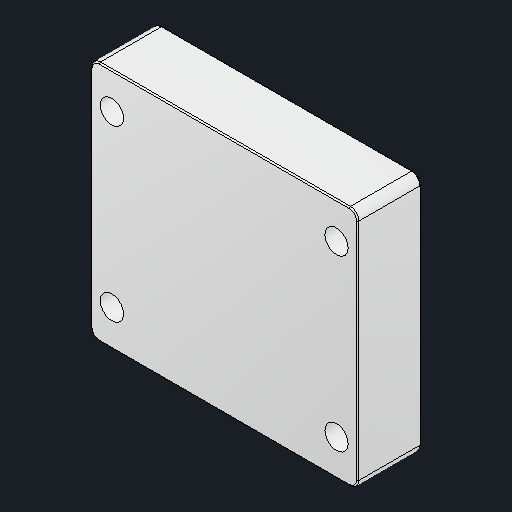
# Autodesk Inventor part: SBI20FL-flat-spacer-15
Saved by Autodesk Inventor 2027.1 (Build 311270010, 270A)
## iProperties
Created: 2026-11-14
Part Number: SBI20FL-flat-spacer-15
Material: Aluminum 6061
Document SubType Name: Modeling
Designer: queezz
Density: 2.7 g/cm^3
Appearance: Aluminum - Flat
Author: queezz
Autodesk Inventor part; units mm, degrees
ref_plane "YZ Plane" through (0, 0, 0) normal (1, 0, 0) x (0, 1, 0)
ref_plane "XZ Plane" through (0, 0, 0) normal (0, 1, 0) x (-1, 0, 0)
sketch "Sketch1" plane through (0, 0, 0) normal (0, 0, 1) x (1, 0, 0)
  line L0 (-31.5, -28.5) -> (31.5, -28.5)
  line L1 (31.5, -28.5) -> (31.5, 28.5)
  line L2 (31.5, 28.5) -> (-31.5, 28.5)
  line L3 (-31.5, 28.5) -> (-31.5, -28.5)
  constraints: 8 end point
extrude "15 mm aluminum plate spacer" add sketch "Sketch1" along normal blind 15
ref_plane "Work Plane1" through (0, 0, 15) normal (0, 0, 1) x (1, 0, 0)
sketch "SBC 53 x 40 mounting pattern" plane through (0, 0, 15) normal (0, 0, 1) x (1, 0, 0)
  circle A0 centre (-26.5, -20) radius 2.75
  circle A1 centre (-26.5, 20) radius 2.75
  circle A2 centre (26.5, -20) radius 2.75
  circle A3 centre (26.5, 20) radius 2.75
  constraints: 4 centre point
extrude "Four straight M5 clearances" cut sketch "SBC 53 x 40 mounting pattern" against normal blind 15
fillet "Fillet1" radius 2 4 edges at (-31.5, -28.5, 7.5) (31.5, -28.5, 7.5) (31.5, 28.5, 7.5) (-31.5, 28.5, 7.5)
chamfer "Chamfer1" distance 0.3 angle 45 16 edges at (-31.5, 0, 15) (-30.9142, -27.9142, 15) (0, -28.5, 15) (30.9142, -27.9142, 15) (31.5, 0, 15) (30.9142, 27.9142, 15) (0, 28.5, 15) (-30.9142, 27.9142, 15) (31.5, 0, 0) (30.9142, 27.9142, 0) (0, 28.5, 0) (-30.9142, 27.9142, 0) (-31.5, 0, 0) (-30.9142, -27.9142, 0) (0, -28.5, 0) (30.9142, -27.9142, 0)
body "Solid1"
